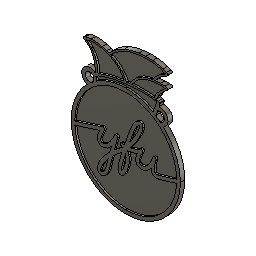
Karnevalsorden (Autodesk Fusion 360 design; units mm, degrees)
Autodesk Fusion 360 part; units mm, degrees
(part 1 of 2)
sketch "Skizze1" plane through (0, 0, 0) normal (0, 0, 1) x (1, 0, 0)
  circle A0 centre (0, 0) radius 30 construction
  spline S0 degree 3 poles (-17.616, 24.4973) (-17.4482, 25.7266) (-17.6451, 26.9772) (-18.1766, 28.0978) knots 0 0 0 0 1 1 1 1
  spline S1 degree 3 poles (-18.1766, 28.0978) (-18.2234, 28.1401) (-18.2504, 28.1872) (-18.216, 28.2338) knots 0 0 0 0 1 1 1 1
  spline S2 degree 3 poles (-18.216, 28.2338) (-18.206, 28.2901) (-18.1253, 28.3306) (-18.0025, 28.3483) knots 0 0 0 0 1 1 1 1
  spline S3 degree 3 poles (-18.0025, 28.3483) (-17.6832, 28.4795) (-17.2924, 28.5436) (-17.0288, 28.7547) knots 0 0 0 0 1 1 1 1
  spline S4 degree 3 poles (-17.0288, 28.7547) (-16.8383, 28.9055) (-16.8992, 29.178) (-16.8992, 29.395) knots 0 0 0 0 1 1 1 1
  spline S5 degree 3 poles (-16.8992, 29.395) (-16.8992, 29.6755) (-16.9122, 29.9401) (-16.9122, 30.2046) knots 0 0 0 0 1 1 1 1
  spline S6 degree 3 poles (-16.9122, 30.2046) (-16.928, 30.7179) (-16.9609, 31.2392) (-17.0103, 31.7683) knots 0 0 0 0 1 1 1 1
  spline S7 degree 3 poles (-17.0103, 31.7683) (-17.0939, 32.675) (-17.244, 33.5744) (-17.4599, 34.4591) knots 0 0 0 0 1 1 1 1
  spline S8 degree 3 poles (-17.4599, 34.4591) (-17.7848, 35.8265) (-18.3203, 37.1351) (-19.0474, 38.3379) knots 0 0 0 0 1 1 1 1
  spline S9 degree 3 poles (-19.0474, 38.3379) (-19.9946, 39.8752) (-21.286, 40.9838) (-22.7174, 42.0421) knots 0 0 0 0 1 1 1 1
  spline S10 degree 3 poles (-22.7174, 42.0421) (-22.982, 42.2352) (-23.4794, 42.526) (-23.5111, 42.8938) knots 0 0 0 0 1 1 1 1
  spline S11 degree 3 poles (-23.5111, 42.8938) (-23.5291, 42.9983) (-23.4712, 43.1023) (-23.3733, 43.1428) knots 0 0 0 0 1 1 1 1
  spline S12 degree 3 poles (-23.3733, 43.1428) (-22.9568, 43.3838) (-22.5126, 43.5727) (-22.0504, 43.7061) knots 0 0 0 0 1 1 1 1
  spline S13 degree 3 poles (-22.0504, 43.7061) (-21.0862, 44.014) (-20.085, 44.1921) (-19.0738, 44.2352) knots 0 0 0 0 1 1 1 1
  spline S14 degree 3 poles (-19.0738, 44.2352) (-17.0386, 44.3223) (-15.0027, 44.0916) (-13.0389, 43.5502) knots 0 0 0 0 1 1 1 1
  spline S15 degree 3 poles (-13.0389, 43.5502) (-12.2002, 43.3174) (-11.3906, 43.021) (-10.5677, 42.7565) knots 0 0 0 0 1 1 1 1
  spline S16 degree 3 poles (-10.5677, 42.7565) (-10.1375, 42.6186) (-9.7131, 42.463) (-9.294, 42.2948) knots 0 0 0 0 1 1 1 1
  spline S17 degree 3 poles (-9.294, 42.2948) (-9.2924, 42.3114) (-9.2961, 42.3281) (-9.2816, 42.3435) knots 0 0 0 0 1 1 1 1
  spline S18 degree 3 poles (-9.2816, 42.3435) (-9.0064, 42.6477) (-8.7262, 42.9443) (-8.4352, 43.2354) knots 0 0 0 0 1 1 1 1
  spline S19 degree 3 poles (-8.4352, 43.2354) (-6.2484, 45.4031) (-3.6817, 47.1504) (-0.8631, 48.3897) knots 0 0 0 0 1 1 1 1
  spline S20 degree 3 poles (-0.8631, 48.3897) (1.7507, 49.5303) (4.5117, 50.2984) (7.339, 50.6725) knots 0 0 0 0 1 1 1 1
  spline S21 degree 3 poles (7.339, 50.6725) (8.5974, 50.8424) (9.8637, 50.9437) (11.131, 50.9755) knots 0 0 0 0 1 1 1 1
  spline S22 degree 3 poles (11.131, 50.9755) (12.3986, 51.0072) (13.6678, 50.9699) (14.9331, 50.8633) knots 0 0 0 0 1 1 1 1
  spline S23 degree 3 poles (14.9331, 50.8633) (16.9063, 50.7289) (18.8571, 50.3593) (20.7428, 49.7626) knots 0 0 0 0 1 1 1 1
  spline S24 degree 3 poles (20.7428, 49.7626) (21.367, 49.5684) (21.9689, 49.3078) (22.5372, 48.985) knots 0 0 0 0 1 1 1 1
  spline S25 degree 3 poles (22.5372, 48.985) (22.9129, 48.8014) (23.2272, 48.5125) (23.4421, 48.154) knots 0 0 0 0 1 1 1 1
  spline S26 degree 3 poles (23.4421, 48.154) (23.4625, 48.1217) (23.4566, 48.0791) (23.4286, 48.0532) knots 0 0 0 0 1 1 1 1
  spline S27 degree 3 poles (23.4286, 48.0532) (22.9338, 47.4076) (22.2435, 47.003) (21.5477, 46.6141) knots 0 0 0 0 1 1 1 1
  spline S28 degree 3 poles (21.5477, 46.6141) (20.8095, 46.2019) (20.102, 45.7367) (19.431, 45.2224) knots 0 0 0 0 1 1 1 1
  spline S29 degree 3 poles (19.431, 45.2224) (18.1673, 44.2572) (17.0572, 43.111) (16.1147, 41.8323) knots 0 0 0 0 1 1 1 1
  spline S30 degree 3 poles (16.1147, 41.8323) (17.172, 41.9148) (18.2306, 41.99) (19.2908, 42.0365) knots 0 0 0 0 1 1 1 1
  spline S31 degree 3 poles (19.2908, 42.0365) (20.1427, 42.0895) (20.9973, 42.0895) (21.8493, 42.0365) knots 0 0 0 0 1 1 1 1
  spline S32 degree 3 poles (21.8493, 42.0365) (22.2382, 41.9889) (23.6191, 41.8857) (23.3783, 41.1952) knots 0 0 0 0 1 1 1 1
  spline S33 degree 3 poles (23.3783, 41.1952) (23.2611, 40.9414) (23.0865, 40.7189) (22.8679, 40.5446) knots 0 0 0 0 1 1 1 1
  spline S34 degree 3 poles (22.8679, 40.5446) (22.561, 40.2456) (22.2327, 39.9807) (21.9072, 39.7161) knots 0 0 0 0 1 1 1 1
  spline S35 degree 3 poles (21.9072, 39.7161) (21.028, 39.0171) (20.2142, 38.2398) (19.4757, 37.3934) knots 0 0 0 0 1 1 1 1
  spline S36 degree 3 poles (19.4757, 37.3934) (18.7878, 36.5724) (18.1819, 35.6863) (17.6662, 34.7475) knots 0 0 0 0 1 1 1 1
  spline S37 degree 3 poles (17.6662, 34.7475) (17.4387, 34.3242) (17.2297, 33.8876) (16.9836, 33.4722) knots 0 0 0 0 1 1 1 1
  spline S38 degree 3 poles (16.9836, 33.4722) (16.9164, 33.3198) (16.8132, 33.1897) (16.6889, 33.0836) knots 0 0 0 0 1 1 1 1
  spline S39 degree 3 poles (16.6889, 33.0836) (17.0786, 32.9642) (17.4749, 32.8595) (17.875, 32.7555) knots 0 0 0 0 1 1 1 1
  spline S40 degree 3 poles (17.875, 32.7555) (18.2052, 32.7007) (18.5288, 32.6121) (18.8407, 32.4909) knots 0 0 0 0 1 1 1 1
  spline S41 degree 3 poles (18.8407, 32.4909) (18.8778, 32.4724) (18.9891, 32.4009) (18.968, 32.3374) knots 0 0 0 0 1 1 1 1
  spline S42 degree 3 poles (18.968, 32.3374) (18.4362, 30.6335) (17.9279, 28.9188) (17.3458, 27.2281) knots 0 0 0 0 1 1 1 1
  spline S43 degree 3 poles (17.3458, 27.2281) (17.1252, 26.588) (16.9135, 25.8274) (16.5002, 25.2646) knots 0 0 0 0 1 1 1 1
  spline S44 degree 3 poles (16.5002, 25.2646) (24.7248, 19.8761) (30.1625, 10.5768) (30.1625, 0.0175) knots 0 0 0 0 1 1 1 1
  spline S45 degree 3 poles (30.1625, 0.0175) (30.1625, -16.6298) (16.6471, -30.1452) (0, -30.1452) knots 0 0 0 0 1 1 1 1
  spline S46 degree 3 poles (0, -30.1452) (-16.6473, -30.1452) (-30.1628, -16.6298) (-30.1628, 0.0175) knots 0 0 0 0 1 1 1 1
  spline S47 degree 3 poles (-30.1628, 0.0175) (-30.1628, 10.0907) (-25.2143, 19.0173) (-17.616, 24.4973) knots 0 0 0 0 1 1 1 1
  spline S48 degree 3 poles (28.1448, -1.3567) (24.9716, -2.4841) (21.4283, -3.5501) (17.957, -4.4156) knots 0 0 0 0 1 1 1 1
  spline S49 degree 3 poles (17.957, -4.4156) (16.2523, -4.8415) (15.3011, -4.2738) (14.8037, -3.7229) knots 0 0 0 0 1 1 1 1
  spline S50 degree 3 poles (14.8037, -3.7229) (14.2669, -3.1286) (14.0248, -2.2828) (13.961, -1.3535) knots 0 0 0 0 1 1 1 1
  spline S51 degree 3 poles (13.961, -1.3535) (12.6484, -3.012) (10.8701, -4.4166) (8.6122, -4.4166) knots 0 0 0 0 1 1 1 1
  spline S52 degree 3 poles (8.6122, -4.4166) (7.0083, -4.4166) (6.2566, -3.6837) (5.9084, -3.0691) knots 0 0 0 0 1 1 1 1
  spline S53 degree 3 poles (5.9084, -3.0691) (5.1385, -1.7097) (5.6534, 0.3541) (6.3328, 2.035) knots 0 0 0 0 1 1 1 1
  spline S54 degree 3 poles (6.3328, 2.035) (4.913, 1.4151) (3.0406, 0.8081) (1.0112, 0.7097) knots 0 0 0 0 1 1 1 1
  spline S55 degree 3 poles (1.0112, 0.7097) (1.3131, 0.2255) (1.547, -0.3264) (1.7087, -0.9421) knots 0 0 0 0 1 1 1 1
  spline S56 degree 3 poles (1.7087, -0.9421) (2.7152, -4.7773) (0.6628, -10.2869) (-1.2121, -12.1298) knots 0 0 0 0 1 1 1 1
  spline S57 degree 3 poles (-1.2121, -12.1298) (-2.032, -12.9357) (-2.73, -12.9574) (-3.171, -12.833) knots 0 0 0 0 1 1 1 1
  spline S58 degree 3 poles (-3.171, -12.833) (-3.5317, -12.7317) (-3.8314, -12.4785) (-4.0148, -12.12) knots 0 0 0 0 1 1 1 1
  spline S59 degree 3 poles (-4.0148, -12.12) (-4.4678, -11.2341) (-4.49, -9.1381) (-2.1275, -1.6486) knots 0 0 0 0 1 1 1 1
  spline S60 degree 3 poles (-2.1275, -1.6486) (-4.1262, -3.1921) (-5.7976, -4.6307) (-7.1911, -5.9565) knots 0 0 0 0 1 1 1 1
  spline S61 degree 3 poles (-7.1911, -5.9565) (-7.3358, -6.473) (-7.4745, -6.9624) (-7.6033, -7.4101) knots 0 0 0 0 1 1 1 1
  spline S62 degree 3 poles (-7.6033, -7.4101) (-7.697, -7.7353) (-7.815, -8.2716) (-7.9518, -8.8926) knots 0 0 0 0 1 1 1 1
  spline S63 degree 3 poles (-7.9518, -8.8926) (-8.7958, -12.7227) (-9.7933, -16.5697) (-11.8637, -17.854) knots 0 0 0 0 1 1 1 1
  spline S64 degree 3 poles (-11.8637, -17.854) (-12.3235, -18.1392) (-12.8222, -18.284) (-13.3331, -18.284) knots 0 0 0 0 1 1 1 1
  spline S65 degree 3 poles (-13.3331, -18.284) (-13.5583, -18.284) (-13.7859, -18.2559) (-14.0134, -18.1993) knots 0 0 0 0 1 1 1 1
  spline S66 degree 3 poles (-14.0134, -18.1993) (-14.8198, -17.999) (-15.3863, -17.3675) (-15.5681, -16.4665) knots 0 0 0 0 1 1 1 1
  spline S67 degree 3 poles (-15.5681, -16.4665) (-16.0004, -14.3234) (-14.3124, -10.2861) (-8.8403, -4.9746) knots 0 0 0 0 1 1 1 1
  spline S68 degree 3 poles (-8.8403, -4.9746) (-8.5548, -3.9488) (-8.2502, -2.8381) (-7.9552, -1.752) knots 0 0 0 0 1 1 1 1
  spline S69 degree 3 poles (-7.9552, -1.752) (-9.2723, -3.2292) (-10.926, -4.4164) (-12.8373, -4.4164) knots 0 0 0 0 1 1 1 1
  spline S70 degree 3 poles (-12.8373, -4.4164) (-14.2777, -4.4164) (-14.9656, -3.7409) (-15.2892, -3.1739) knots 0 0 0 0 1 1 1 1
  spline S71 degree 3 poles (-15.2892, -3.1739) (-16.1496, -1.6668) (-15.3331, 0.8417) (-14.5137, 2.6544) knots 0 0 0 0 1 1 1 1
  spline S72 degree 3 poles (-14.5137, 2.6544) (-17.9602, 1.5426) (-24.6946, -0.6209) (-28.1286, -1.6639) knots 0 0 0 0 1 1 1 1
  spline S73 degree 3 poles (-28.1286, -1.6639) (-27.2576, -16.4345) (-14.9876, -28.1609) (-0.0003, -28.1609) knots 0 0 0 0 1 1 1 1
  spline S74 degree 3 poles (-0.0003, -28.1609) (15.0916, -28.1609) (27.428, -16.271) (28.1448, -1.3567) knots 0 0 0 0 1 1 1 1
  spline S75 degree 3 poles (-12.8408, -16.2803) (-13.0813, -16.4295) (-13.3054, -16.4671) (-13.5676, -16.402) knots 0 0 0 0 1 1 1 1
  spline S76 degree 3 poles (-13.5676, -16.402) (-13.6067, -16.3922) (-13.6991, -16.3692) (-13.7533, -16.1004) knots 0 0 0 0 1 1 1 1
  spline S77 degree 3 poles (-13.7533, -16.1004) (-13.9348, -15.2013) (-13.2816, -12.6174) (-9.7959, -8.65) knots 0 0 0 0 1 1 1 1
  spline S78 degree 3 poles (-9.7959, -8.65) (-10.2952, -10.9127) (-11.2974, -15.323) (-12.8408, -16.2803) knots 0 0 0 0 1 1 1 1
  spline S79 degree 3 poles (-2.417, -10.7449) (-2.3987, -9.8541) (-2.0709, -7.6197) (-0.3418, -2.1333) knots 0 0 0 0 1 1 1 1
  spline S80 degree 3 poles (-0.3418, -2.1333) (-0.2609, -1.8761) (-0.1786, -1.6181) (-0.0958, -1.3602) knots 0 0 0 0 1 1 1 1
  spline S81 degree 3 poles (-0.0958, -1.3602) (0.0341, -1.8338) (0.1058, -2.3701) (0.1193, -2.9688) knots 0 0 0 0 1 1 1 1
  spline S82 degree 3 poles (0.1193, -2.9688) (0.1924, -6.1959) (-1.4219, -9.6967) (-2.417, -10.7449) knots 0 0 0 0 1 1 1 1
  spline S83 degree 3 poles (28.1715, 0.621) (27.8492, 15.8954) (15.3495, 28.1957) (-0.0003, 28.1957) knots 0 0 0 0 1 1 1 1
  spline S84 degree 3 poles (-0.0003, 28.1957) (-15.4712, 28.1957) (-28.0469, 15.7002) (-28.1771, 0.2578) knots 0 0 0 0 1 1 1 1
  spline S85 degree 3 poles (-28.1771, 0.2578) (-23.2635, 1.7638) (-13.058, 5.0711) (-12.945, 5.1078) knots 0 0 0 0 1 1 1 1
  spline S86 degree 3 poles (-12.945, 5.1078) (-12.5786, 5.2266) (-12.1777, 5.1063) (-11.9369, 4.806) knots 0 0 0 0 1 1 1 1
  spline S87 degree 3 poles (-11.9369, 4.806) (-11.6964, 4.5059) (-11.6665, 4.0879) (-11.8618, 3.7564) knots 0 0 0 0 1 1 1 1
  spline S88 degree 3 poles (-11.8618, 3.7564) (-12.9379, 1.9307) (-14.2602, -1.2427) (-13.6811, -2.256) knots 0 0 0 0 1 1 1 1
  spline S89 degree 3 poles (-13.6811, -2.256) (-13.6374, -2.3325) (-13.5046, -2.5645) (-12.8376, -2.5645) knots 0 0 0 0 1 1 1 1
  spline S90 degree 3 poles (-12.8376, -2.5645) (-9.7613, -2.5645) (-7.0427, 2.5845) (-6.2547, 4.5686) knots 0 0 0 0 1 1 1 1
  spline S91 degree 3 poles (-6.2547, 4.5686) (-6.0738, 5.0237) (-5.5703, 5.2595) (-5.1043, 5.1063) knots 0 0 0 0 1 1 1 1
  spline S92 degree 3 poles (-5.1043, 5.1063) (-4.6389, 4.9531) (-4.3733, 4.4639) (-4.4984, 3.9902) knots 0 0 0 0 1 1 1 1
  spline S93 degree 3 poles (-4.4984, 3.9902) (-4.5114, 3.9413) (-5.3668, 0.7039) (-6.2767, -2.6378) knots 0 0 0 0 1 1 1 1
  spline S94 degree 3 poles (-6.2767, -2.6378) (-5.044, -1.5776) (-3.6695, -0.4749) (-2.1434, 0.665) knots 0 0 0 0 1 1 1 1
  spline S95 degree 3 poles (-2.1434, 0.665) (-2.0529, 0.7324) (-1.96, 0.8047) (-1.8658, 0.8811) knots 0 0 0 0 1 1 1 1
  spline S96 degree 3 poles (-1.8658, 0.8811) (-2.0169, 0.9526) (-2.1765, 1.0142) (-2.3445, 1.0663) knots 0 0 0 0 1 1 1 1
  spline S97 degree 3 poles (-2.3445, 1.0663) (-2.3998, 1.0819) (-2.4553, 1.0981) (-2.5106, 1.1145) knots 0 0 0 0 1 1 1 1
  spline S98 degree 3 poles (-2.5106, 1.1145) (-2.9961, 1.2592) (-3.275, 1.7675) (-3.1366, 2.2548) knots 0 0 0 0 1 1 1 1
  spline S99 degree 3 poles (-3.1366, 2.2548) (-2.9983, 2.7422) (-2.4934, 3.029) (-2.0047, 2.8959) knots 0 0 0 0 1 1 1 1
  spline S100 degree 3 poles (-2.0047, 2.8959) (-1.9434, 2.8795) (-1.8828, 2.8621) (-1.8225, 2.8438) knots 0 0 0 0 1 1 1 1
  spline S101 degree 3 poles (-1.8225, 2.8438) (-1.4555, 2.7427) (-1.0869, 2.6705) (-0.7191, 2.6226) knots 0 0 0 0 1 1 1 1
  spline S102 degree 3 poles (-0.7191, 2.6226) (-0.0122, 4.6909) (0.826, 7.0539) (1.8148, 9.7534) knots 0 0 0 0 1 1 1 1
  spline S103 degree 3 poles (1.8148, 9.7534) (1.9476, 10.1161) (2.0548, 10.4085) (2.1304, 10.6181) knots 0 0 0 0 1 1 1 1
  spline S104 degree 3 poles (2.1304, 10.6181) (3.6716, 14.8823) (5.2631, 17.2956) (6.8601, 17.7909) knots 0 0 0 0 1 1 1 1
  spline S105 degree 3 poles (6.8601, 17.7909) (7.543, 18.002) (8.2219, 17.8862) (8.8236, 17.4546) knots 0 0 0 0 1 1 1 1
  spline S106 degree 3 poles (8.8236, 17.4546) (9.1324, 17.2332) (9.502, 16.7876) (9.5102, 15.9222) knots 0 0 0 0 1 1 1 1
  spline S107 degree 3 poles (9.5102, 15.9222) (9.5348, 13.356) (6.0074, 7.0859) (2.481, 2.7525) knots 0 0 0 0 1 1 1 1
  spline S108 degree 3 poles (2.481, 2.7525) (5.5062, 3.3335) (7.8941, 4.9634) (7.9288, 4.9877) knots 0 0 0 0 1 1 1 1
  spline S109 degree 3 poles (7.9288, 4.9877) (8.2873, 5.2359) (8.7701, 5.2007) (9.0887, 4.9028) knots 0 0 0 0 1 1 1 1
  spline S110 degree 3 poles (9.0887, 4.9028) (9.4073, 4.6051) (9.4747, 4.1252) (9.2506, 3.7508) knots 0 0 0 0 1 1 1 1
  spline S111 degree 3 poles (9.2506, 3.7508) (8.1986, 1.9929) (6.921, -1.1009) (7.5197, -2.1568) knots 0 0 0 0 1 1 1 1
  spline S112 degree 3 poles (7.5197, -2.1568) (7.5769, -2.2576) (7.751, -2.5645) (8.6117, -2.5645) knots 0 0 0 0 1 1 1 1
  spline S113 degree 3 poles (8.6117, -2.5645) (11.7758, -2.5645) (14.0769, 1.9371) (14.8741, 4.1167) knots 0 0 0 0 1 1 1 1
  spline S114 degree 3 poles (14.8741, 4.1167) (14.9333, 4.2953) (14.9839, 4.439) (15.0207, 4.5411) knots 0 0 0 0 1 1 1 1
  spline S115 degree 3 poles (15.0207, 4.5411) (15.1921, 5.0166) (15.7125, 5.2661) (16.1914, 5.1031) knots 0 0 0 0 1 1 1 1
  spline S116 degree 3 poles (16.1914, 5.1031) (16.6695, 4.9393) (16.9283, 4.4226) (16.7727, 3.9416) knots 0 0 0 0 1 1 1 1
  spline S117 degree 3 poles (16.7727, 3.9416) (16.7614, 3.9066) (16.7235, 3.7913) (16.6584, 3.6119) knots 0 0 0 0 1 1 1 1
  spline S118 degree 3 poles (16.6584, 3.6119) (15.9695, 1.5582) (15.3808, -1.6001) (16.1777, -2.4817) knots 0 0 0 0 1 1 1 1
  spline S119 degree 3 poles (16.1777, -2.4817) (16.4071, -2.7355) (16.855, -2.7818) (17.5083, -2.6188) knots 0 0 0 0 1 1 1 1
  spline S120 degree 3 poles (17.5083, -2.6188) (21.1622, -1.7073) (24.8946, -0.5717) (28.1715, 0.621) knots 0 0 0 0 1 1 1 1
  spline S121 degree 3 poles (3.5534, 9.1163) (3.6872, 9.4822) (3.7954, 9.7772) (3.8719, 9.9886) knots 0 0 0 0 1 1 1 1
  spline S122 degree 3 poles (3.8719, 9.9886) (5.3552, 14.0926) (6.7043, 15.8039) (7.4086, 16.0222) knots 0 0 0 0 1 1 1 1
  spline S123 degree 3 poles (7.4086, 16.0222) (7.4433, 16.0328) (7.4792, 16.0431) (7.5155, 16.0415) knots 0 0 0 0 1 1 1 1
  spline S124 degree 3 poles (7.5155, 16.0415) (7.5642, 16.0394) (7.6015, 16.0317) (7.6565, 16.0037) knots 0 0 0 0 1 1 1 1
  spline S125 degree 3 poles (7.6565, 16.0037) (7.7478, 15.4322) (7.148, 13.1366) (4.6027, 8.971) knots 0 0 0 0 1 1 1 1
  spline S126 degree 3 poles (4.6027, 8.971) (3.8394, 7.7219) (3.0274, 6.5186) (2.2148, 5.4203) knots 0 0 0 0 1 1 1 1
  spline S127 degree 3 poles (2.2148, 5.4203) (2.7525, 6.9295) (3.2247, 8.2191) (3.5534, 9.1163) knots 0 0 0 0 1 1 1 1
  spline S128 degree 3 poles (15.0596, 26.152) (10.6273, 28.7134) (5.4835, 30.18) (0, 30.18) knots 0 0 0 0 1 1 1 1
  spline S129 degree 3 poles (0, 30.18) (-5.9664, 30.18) (-11.5305, 28.4438) (-16.2139, 25.4498) knots 0 0 0 0 1 1 1 1
  spline S130 degree 3 poles (-16.2139, 25.4498) (-16.3237, 26.1592) (-16.3161, 26.8923) (-16.5132, 27.5858) knots 0 0 0 0 1 1 1 1
  spline S131 degree 3 poles (-16.5132, 27.5858) (-14.6418, 28.923) (-12.3076, 29.6376) (-10.1126, 30.2388) knots 0 0 0 0 1 1 1 1
  spline S132 degree 3 poles (-10.1126, 30.2388) (-7.775, 30.8679) (-5.4054, 31.3717) (-3.0139, 31.7472) knots 0 0 0 0 1 1 1 1
  spline S133 degree 3 poles (-3.0139, 31.7472) (0.3421, 32.302) (3.7293, 32.6502) (7.1279, 32.7896) knots 0 0 0 0 1 1 1 1
  spline S134 degree 3 poles (7.1279, 32.7896) (7.9923, 32.8227) (8.8643, 32.8446) (9.7385, 32.8468) knots 0 0 0 0 1 1 1 1
  spline S135 degree 3 poles (9.7385, 32.8468) (12.228, 32.8528) (14.7352, 32.6877) (17.1508, 32.1472) knots 0 0 0 0 1 1 1 1
  spline S136 degree 3 poles (17.1508, 32.1472) (16.4716, 30.3094) (15.948, 28.4176) (15.2188, 26.6007) knots 0 0 0 0 1 1 1 1
  spline S137 degree 3 poles (15.2188, 26.6007) (15.177, 26.4939) (15.1257, 26.3219) (15.0596, 26.152) knots 0 0 0 0 1 1 1 1
  spline S138 degree 3 poles (-17.5363, 43.233) (-16.1285, 43.2409) (-14.7238, 43.084) (-13.3511, 42.7641) knots 0 0 0 0 1 1 1 1
  spline S139 degree 3 poles (-13.3511, 42.7641) (-9.8904, 41.9916) (-6.4717, 40.399) (-3.9423, 37.8852) knots 0 0 0 0 1 1 1 1
  spline S140 degree 3 poles (-3.9423, 37.8852) (-2.5643, 36.5562) (-1.5401, 34.906) (-0.9538, 33.0846) knots 0 0 0 0 1 1 1 1
  spline S141 degree 3 poles (-0.9538, 33.0846) (-2.5556, 32.7084) (-4.182, 32.4695) (-5.7944, 32.184) knots 0 0 0 0 1 1 1 1
  spline S142 degree 3 poles (-5.7944, 32.184) (-7.833, 31.8371) (-9.8467, 31.3556) (-11.8221, 30.7441) knots 0 0 0 0 1 1 1 1
  spline S143 degree 3 poles (-11.8221, 30.7441) (-13.0127, 30.3697) (-14.1856, 29.9453) (-15.3469, 29.4858) knots 0 0 0 0 1 1 1 1
  spline S144 degree 3 poles (-15.3469, 29.4858) (-15.3924, 31.331) (-15.6768, 33.1629) (-16.1981, 34.9351) knots 0 0 0 0 1 1 1 1
  spline S145 degree 3 poles (-16.1981, 34.9351) (-16.7918, 36.8025) (-17.785, 38.5178) (-19.1085, 39.9622) knots 0 0 0 0 1 1 1 1
  spline S146 degree 3 poles (-19.1085, 39.9622) (-19.9379, 40.8576) (-20.8642, 41.6577) (-21.866, 42.3551) knots 0 0 0 0 1 1 1 1
  spline S147 degree 3 poles (-21.866, 42.3551) (-20.696, 42.893) (-19.4286, 43.1893) (-18.1398, 43.2198) knots 0 0 0 0 1 1 1 1
  spline S148 degree 3 poles (-18.1398, 43.2198) (-17.9387, 43.2274) (-17.7374, 43.2319) (-17.5363, 43.233) knots 0 0 0 0 1 1 1 1
  spline S149 degree 3 poles (13.1352, 49.9976) (13.694, 49.9904) (14.2534, 49.9658) (14.8135, 49.919) knots 0 0 0 0 1 1 1 1
  spline S150 degree 3 poles (14.8135, 49.919) (17.2601, 49.7124) (19.6596, 49.0932) (21.7734, 47.8396) knots 0 0 0 0 1 1 1 1
  spline S151 degree 3 poles (21.7734, 47.8396) (19.8072, 46.7763) (18.0078, 45.4288) (16.4383, 43.8362) knots 0 0 0 0 1 1 1 1
  spline S152 degree 3 poles (16.4383, 43.8362) (16.0327, 43.4182) (15.6483, 42.9824) (15.285, 42.5292) knots 0 0 0 0 1 1 1 1
  spline S153 degree 3 poles (15.285, 42.5292) (15.1236, 42.3281) (15.0201, 42.1238) (14.8455, 41.9415) knots 0 0 0 0 1 1 1 1
  spline S154 degree 3 poles (14.8455, 41.9415) (14.6442, 41.7661) (14.4052, 41.6391) (14.147, 41.5709) knots 0 0 0 0 1 1 1 1
  spline S155 degree 3 poles (14.147, 41.5709) (13.2183, 41.2904) (12.2449, 41.1613) (11.3109, 40.8938) knots 0 0 0 0 1 1 1 1
  spline S156 degree 3 poles (11.3109, 40.8938) (9.8803, 40.4945) (8.5222, 39.8693) (7.289, 39.0417) knots 0 0 0 0 1 1 1 1
  spline S157 degree 3 poles (7.289, 39.0417) (5.1935, 37.6185) (3.5187, 35.6868) (2.1243, 33.5884) knots 0 0 0 0 1 1 1 1
  spline S158 degree 3 poles (2.1243, 33.5884) (2.1111, 33.5704) (2.1042, 33.549) (2.1042, 33.5265) knots 0 0 0 0 1 1 1 1
  spline S159 degree 3 poles (2.1042, 33.5265) (2.1042, 33.5146) (2.1093, 33.5037) (2.113, 33.4931) knots 0 0 0 0 1 1 1 1
  spline S160 degree 3 poles (2.113, 33.4931) (1.5452, 33.4384) (0.9784, 33.3728) (0.412, 33.3021) knots 0 0 0 0 1 1 1 1
  spline S161 degree 3 poles (0.412, 33.3021) (-1.2692, 36.8801) (-4.228, 39.7966) (-7.7391, 41.5897) knots 0 0 0 0 1 1 1 1
  spline S162 degree 3 poles (-7.7391, 41.5897) (-8.0063, 41.7262) (-8.2775, 41.8545) (-8.5508, 41.9781) knots 0 0 0 0 1 1 1 1
  spline S163 degree 3 poles (-8.5508, 41.9781) (-8.4463, 41.9873) (-8.3497, 42.0111) (-8.2868, 42.0715) knots 0 0 0 0 1 1 1 1
  spline S164 degree 3 poles (-8.2868, 42.0715) (-5.4054, 44.8705) (-2.0458, 47.1697) (1.7828, 48.4638) knots 0 0 0 0 1 1 1 1
  spline S165 degree 3 poles (1.7828, 48.4638) (3.8349, 49.1356) (5.9597, 49.5623) (8.1121, 49.7341) knots 0 0 0 0 1 1 1 1
  spline S166 degree 3 poles (8.1121, 49.7341) (9.7869, 49.8849) (11.4586, 50.019) (13.1352, 49.9976) knots 0 0 0 0 1 1 1 1
  spline S167 degree 3 poles (18.6288, 41.1362) (19.648, 41.1552) (20.6655, 41.066) (21.6704, 40.8906) knots 0 0 0 0 1 1 1 1
  spline S168 degree 3 poles (21.6704, 40.8906) (20.5936, 39.8124) (19.4352, 38.8134) (18.4042, 37.6871) knots 0 0 0 0 1 1 1 1
  spline S169 degree 3 poles (18.4042, 37.6871) (17.2262, 36.3972) (16.2764, 34.9174) (15.5893, 33.3122) knots 0 0 0 0 1 1 1 1
  spline S170 degree 3 poles (15.5893, 33.3122) (11.5356, 33.8114) (7.4456, 33.9072) (3.3782, 33.5995) knots 0 0 0 0 1 1 1 1
  spline S171 degree 3 poles (3.3782, 33.5995) (4.1693, 34.4943) (4.8025, 35.5236) (5.6065, 36.4067) knots 0 0 0 0 1 1 1 1
  spline S172 degree 3 poles (5.6065, 36.4067) (6.6072, 37.4711) (7.7957, 38.3422) (9.1122, 38.9758) knots 0 0 0 0 1 1 1 1
  spline S173 degree 3 poles (9.1122, 38.9758) (11.6467, 40.2749) (14.6182, 40.8626) (17.4387, 41.069) knots 0 0 0 0 1 1 1 1
  spline S174 degree 3 poles (17.4387, 41.069) (17.835, 41.1063) (18.2319, 41.1285) (18.6288, 41.1362) knots 0 0 0 0 1 1 1 1
  arc A1 (14.4395, 26.5006) -> (14.4198, 26.3072) centre (18.9053, 25.9469) ccw
  arc A2 (20.6228, 21.7876) -> (18.3737, 30.4154) centre (18.9053, 25.9469) ccw
  arc A3 (18.9867, 23.4482) -> (17.6404, 28.1033) centre (18.9053, 25.9469) ccw
  arc A4 (-16.8935, 29.0389) -> (-21.1061, 21.3197) centre (-19.8405, 25.6381) ccw
  arc A5 (-15.3427, 25.7798) -> (-15.3535, 25.9798) centre (-19.8405, 25.6381) ccw
  arc A6 (-17.7936, 27.0735) -> (-19.2887, 23.1997) centre (-19.8405, 25.6381) ccw
  dimension "d1" = 60
  dimension "d2" = 5
  dimension "d4" = 5
  constraint coincident A0.centre origin
  constraint coincident S43.end A3
  constraint concentric A1 A3
  constraint coincident S42 A2.end
  constraint coincident S128 A1.start
  constraint coincident A0 A1.end
  constraint concentric A1 A2
  constraint coincident A0 A2.start
  constraint coincident S42 A3.end
  constraint concentric A4 A6
  constraint coincident S4 A4.start
  constraint coincident S129 A5.end
  constraint coincident A0 A5.start
  constraint concentric A4 A5
  constraint coincident A0 A4.end
  constraint coincident S47 A6.end
  constraint coincident S0 A6.start
  constraint coincident S44 A3.start
  measures "d1" diameter of A0
  measures "d2" diameter of A3
  measures "d4" diameter of A6
extrude "Extrusion1" add sketch "Skizze1" against normal blind 1.5 contours S0 S1 S2 S3 S4 S5 S6 S7 S8 S9 S10 S11 S12 S13 S14 S15 S16 S17 S18 S19 S20 S21 S22 S23 S24 S25 S26 S27 S28 S29 S30 S31 S32 S33 S34 S35 S36 S37 S38 S39 S40 S41 S42 S43 S44 S45 S46 S47 | S0 S1 S2 S3 S4 S47 A4 A6 | S42 S44 A2 A3 | S48 S49 S50 S51 S52 S53 S54 S55 S56 S57 S58 S59 S60 S61 S62 S63 S64 S65 S66 S67 S68 S69 S70 S71 S72 S73 S74 | S75 S76 S77 S78 | S79 S80 S81 S82 | S83 S84 S85 S86 S87 S88 S89 S90 S91 S92 S93 S94 S95 S96 S97 S98 S99 S100 S101 S102 S103 S104 S105 S106 S107 S108 S109 S110 S111 S112 S113 S114 S115 S116 S117 S118 S119 S120 | S121 S122 S123 S124 S125 S126 S127 | S128 S129 S130 S131 S132 S133 S134 S135 S136 S137 | S138 S139 S140 S141 S142 S143 S144 S145 S146 S147 S148 | S149 S150 S151 S152 S153 S154 S155 S156 S157 S158 S159 S160 S161 S162 S163 S164 S165 S166 | S167 S168 S169 S170 S171 S172 S173 S174 makes body 1
extrude "Extrusion2" add sketch "Skizze1" along normal blind 1 contours S0 S1 S2 S3 S4 S5 S6 S7 S8 S9 S10 S11 S12 S13 S14 S15 S16 S17 S18 S19 S20 S21 S22 S23 S24 S25 S26 S27 S28 S29 S30 S31 S32 S33 S34 S35 S36 S37 S38 S39 S40 S41 S42 S43 S44 S45 S46 S47 | S0 S1 S2 S3 S4 S47 A4 A6 | S42 S44 A2 A3 bodies 1
sketch "Skizze2" plane through (0, 0, 0) normal (0, 0, 1) x (1, 0, 0)
  circle A0 centre (0, 0) radius 30 construction
  spline S0 degree 3 poles (-17.4432, 23.7028) (-17.4688, 23.7319) (-17.4815, 23.7663) (-17.4763, 23.8068) knots 0 0 0 0 1 1 1 1
  spline S1 degree 3 poles (-17.4763, 23.8068) (-17.2897, 25.0604) (-17.4837, 26.3397) (-18.0261, 27.4835) knots 0 0 0 0 1 1 1 1
  spline S2 degree 3 poles (-18.0261, 27.4835) (-18.0729, 27.5258) (-18.0999, 27.5729) (-18.0655, 27.6195) knots 0 0 0 0 1 1 1 1
  spline S3 degree 3 poles (-18.0655, 27.6195) (-18.0554, 27.6758) (-17.9747, 27.7163) (-17.852, 27.734) knots 0 0 0 0 1 1 1 1
  spline S4 degree 3 poles (-17.852, 27.734) (-17.5326, 27.8653) (-17.1418, 27.9293) (-16.8783, 28.1404) knots 0 0 0 0 1 1 1 1
  spline S5 degree 3 poles (-16.8783, 28.1404) (-16.6878, 28.2912) (-16.7487, 28.5638) (-16.7487, 28.7807) knots 0 0 0 0 1 1 1 1
  spline S6 degree 3 poles (-16.7487, 28.7807) (-16.7487, 29.0612) (-16.7616, 29.3258) (-16.7616, 29.5903) knots 0 0 0 0 1 1 1 1
  spline S7 degree 3 poles (-16.7616, 29.5903) (-16.7775, 30.1036) (-16.8103, 30.6249) (-16.8598, 31.154) knots 0 0 0 0 1 1 1 1
  spline S8 degree 3 poles (-16.8598, 31.154) (-16.9434, 32.0608) (-17.0934, 32.9601) (-17.3093, 33.8448) knots 0 0 0 0 1 1 1 1
  spline S9 degree 3 poles (-17.3093, 33.8448) (-17.6342, 35.2122) (-18.1697, 36.5208) (-18.8968, 37.7236) knots 0 0 0 0 1 1 1 1
  spline S10 degree 3 poles (-18.8968, 37.7236) (-19.844, 39.2609) (-21.1354, 40.3695) (-22.5668, 41.4278) knots 0 0 0 0 1 1 1 1
  spline S11 degree 3 poles (-22.5668, 41.4278) (-22.8314, 41.6209) (-23.3288, 41.9117) (-23.3606, 42.2795) knots 0 0 0 0 1 1 1 1
  spline S12 degree 3 poles (-23.3606, 42.2795) (-23.3786, 42.384) (-23.3206, 42.488) (-23.2227, 42.5285) knots 0 0 0 0 1 1 1 1
  spline S13 degree 3 poles (-23.2227, 42.5285) (-22.8063, 42.7695) (-22.3621, 42.9584) (-21.8998, 43.0918) knots 0 0 0 0 1 1 1 1
  spline S14 degree 3 poles (-21.8998, 43.0918) (-20.9357, 43.3997) (-19.9345, 43.5778) (-18.9233, 43.6209) knots 0 0 0 0 1 1 1 1
  spline S15 degree 3 poles (-18.9233, 43.6209) (-16.8881, 43.708) (-14.8521, 43.4773) (-12.8884, 42.9359) knots 0 0 0 0 1 1 1 1
  spline S16 degree 3 poles (-12.8884, 42.9359) (-12.0497, 42.7031) (-11.24, 42.4068) (-10.4172, 42.1422) knots 0 0 0 0 1 1 1 1
  spline S17 degree 3 poles (-10.4172, 42.1422) (-9.987, 42.0043) (-9.5626, 41.8488) (-9.1435, 41.6805) knots 0 0 0 0 1 1 1 1
  spline S18 degree 3 poles (-9.1435, 41.6805) (-9.1419, 41.6971) (-9.1456, 41.7138) (-9.131, 41.7292) knots 0 0 0 0 1 1 1 1
  spline S19 degree 3 poles (-9.131, 41.7292) (-8.8559, 42.0334) (-8.5757, 42.33) (-8.2846, 42.6211) knots 0 0 0 0 1 1 1 1
  spline S20 degree 3 poles (-8.2846, 42.6211) (-6.0979, 44.7888) (-3.5311, 46.5361) (-0.7125, 47.7754) knots 0 0 0 0 1 1 1 1
  spline S21 degree 3 poles (-0.7125, 47.7754) (1.9013, 48.916) (4.6622, 49.6841) (7.4896, 50.0582) knots 0 0 0 0 1 1 1 1
  spline S22 degree 3 poles (7.4896, 50.0582) (8.7479, 50.2281) (10.0142, 50.3294) (11.2816, 50.3612) knots 0 0 0 0 1 1 1 1
  spline S23 degree 3 poles (11.2816, 50.3612) (12.5492, 50.3929) (13.8184, 50.3556) (15.0836, 50.249) knots 0 0 0 0 1 1 1 1
  spline S24 degree 3 poles (15.0836, 50.249) (17.0569, 50.1146) (19.0077, 49.745) (20.8934, 49.1483) knots 0 0 0 0 1 1 1 1
  spline S25 degree 3 poles (20.8934, 49.1483) (21.5175, 48.9541) (22.1194, 48.6935) (22.6878, 48.3707) knots 0 0 0 0 1 1 1 1
  spline S26 degree 3 poles (22.6878, 48.3707) (23.0635, 48.1871) (23.3778, 47.8982) (23.5926, 47.5397) knots 0 0 0 0 1 1 1 1
  spline S27 degree 3 poles (23.5926, 47.5397) (23.613, 47.5074) (23.6072, 47.4648) (23.5791, 47.4389) knots 0 0 0 0 1 1 1 1
  spline S28 degree 3 poles (23.5791, 47.4389) (23.0844, 46.7933) (22.3941, 46.3887) (21.6982, 45.9998) knots 0 0 0 0 1 1 1 1
  spline S29 degree 3 poles (21.6982, 45.9998) (20.96, 45.5876) (20.2525, 45.1224) (19.5815, 44.6081) knots 0 0 0 0 1 1 1 1
  spline S30 degree 3 poles (19.5815, 44.6081) (18.3179, 43.6429) (17.2077, 42.4967) (16.2653, 41.218) knots 0 0 0 0 1 1 1 1
  spline S31 degree 3 poles (16.2653, 41.218) (17.3225, 41.3005) (18.3811, 41.3757) (19.4413, 41.4222) knots 0 0 0 0 1 1 1 1
  spline S32 degree 3 poles (19.4413, 41.4222) (20.2933, 41.4752) (21.1479, 41.4752) (21.9998, 41.4222) knots 0 0 0 0 1 1 1 1
  spline S33 degree 3 poles (21.9998, 41.4222) (22.3888, 41.3746) (23.7696, 41.2714) (23.5289, 40.5809) knots 0 0 0 0 1 1 1 1
  spline S34 degree 3 poles (23.5289, 40.5809) (23.4117, 40.3271) (23.237, 40.1046) (23.0185, 39.9303) knots 0 0 0 0 1 1 1 1
  spline S35 degree 3 poles (23.0185, 39.9303) (22.7116, 39.6313) (22.3832, 39.3664) (22.0578, 39.1018) knots 0 0 0 0 1 1 1 1
  spline S36 degree 3 poles (22.0578, 39.1018) (21.1786, 38.4028) (20.3647, 37.6255) (19.6263, 36.7791) knots 0 0 0 0 1 1 1 1
  spline S37 degree 3 poles (19.6263, 36.7791) (18.9383, 35.9581) (18.3325, 35.072) (17.8168, 34.1332) knots 0 0 0 0 1 1 1 1
  spline S38 degree 3 poles (17.8168, 34.1332) (17.5892, 33.7099) (17.3802, 33.2733) (17.1342, 32.8579) knots 0 0 0 0 1 1 1 1
  spline S39 degree 3 poles (17.1342, 32.8579) (17.0669, 32.7055) (16.9638, 32.5754) (16.8394, 32.4693) knots 0 0 0 0 1 1 1 1
  spline S40 degree 3 poles (16.8394, 32.4693) (17.2291, 32.3499) (17.6255, 32.2452) (18.0255, 32.1412) knots 0 0 0 0 1 1 1 1
  spline S41 degree 3 poles (18.0255, 32.1412) (18.3557, 32.0864) (18.6793, 31.9978) (18.9913, 31.8766) knots 0 0 0 0 1 1 1 1
  spline S42 degree 3 poles (18.9913, 31.8766) (19.0283, 31.8581) (19.1397, 31.7866) (19.1185, 31.7231) knots 0 0 0 0 1 1 1 1
  spline S43 degree 3 poles (19.1185, 31.7231) (18.5867, 30.0192) (18.0784, 28.3045) (17.4964, 26.6138) knots 0 0 0 0 1 1 1 1
  spline S44 degree 3 poles (17.4964, 26.6138) (17.2582, 25.9232) (17.0307, 25.0924) (16.5492, 24.5209) knots 0 0 0 0 1 1 1 1
  spline S45 degree 3 poles (16.5492, 24.5209) (16.5145, 24.4804) (16.4801, 24.4431) (16.446, 24.409) knots 0 0 0 0 1 1 1 1
  spline S46 degree 3 poles (16.446, 24.409) (24.2414, 19.1269) (29.3688, 10.1972) (29.3688, 0.0798) knots 0 0 0 0 1 1 1 1
  spline S47 degree 3 poles (29.3688, 0.0798) (29.3688, -16.1294) (16.2092, -29.289) (0, -29.289) knots 0 0 0 0 1 1 1 1
  spline S48 degree 3 poles (0, -29.289) (-16.2089, -29.289) (-29.3688, -16.1294) (-29.3688, 0.0798) knots 0 0 0 0 1 1 1 1
  spline S49 degree 3 poles (-29.3688, 0.0798) (-29.3688, 9.7596) (-24.6753, 18.3522) (-17.4432, 23.7028) knots 0 0 0 0 1 1 1 1
  spline S50 degree 3 poles (23.7546, -14.3247) (17.013, -15.963) (9.0474, -17.3539) (2.3191, -17.3541) knots 0 0 0 0 1 1 1 1
  spline S51 degree 3 poles (2.3191, -17.3541) (-2.6136, -17.3541) (-6.88, -16.607) (-9.5123, -14.662) knots 0 0 0 0 1 1 1 1
  spline S52 degree 3 poles (-9.5123, -14.662) (-9.8274, -14.4289) (-10.1169, -14.1821) (-10.3799, -13.9209) knots 0 0 0 0 1 1 1 1
  spline S53 degree 3 poles (-10.3799, -13.9209) (-15.5173, -14.8083) (-20.4359, -14.6065) (-23.8416, -14.1805) knots 0 0 0 0 1 1 1 1
  spline S54 degree 3 poles (-23.8416, -14.1805) (-18.9854, -22.277) (-10.1211, -27.7012) (0, -27.7012) knots 0 0 0 0 1 1 1 1
  spline S55 degree 3 poles (0, -27.7012) (10.06, -27.7012) (18.8783, -22.3426) (23.7546, -14.3247) knots 0 0 0 0 1 1 1 1
  spline S56 degree 3 poles (24.9499, -12.1448) (26.7631, -8.4546) (27.7813, -4.3052) (27.7813, 0.08) knots 0 0 0 0 1 1 1 1
  spline S57 degree 3 poles (27.7813, 0.08) (27.7813, 15.4126) (15.3329, 27.861) (0, 27.861) knots 0 0 0 0 1 1 1 1
  spline S58 degree 3 poles (0, 27.861) (-0.871, 27.861) (-1.7328, 27.8208) (-2.5852, 27.742) knots 0 0 0 0 1 1 1 1
  line L0 (-2.5852, 27.742) -> (-3.9293, 27.5845)
  spline S59 degree 3 poles (-3.9293, 27.5845) (-17.4048, 25.6732) (-27.7812, 14.0786) (-27.7812, 0.08) knots 0 0 0 0 1 1 1 1
  spline S60 degree 3 poles (-27.7812, 0.08) (-27.7812, -4.3176) (-26.7573, -8.4776) (-24.9343, -12.176) knots 0 0 0 0 1 1 1 1
  spline S61 degree 3 poles (-24.9343, -12.176) (-21.9083, -12.6689) (-16.9299, -13.0576) (-11.6083, -12.2646) knots 0 0 0 0 1 1 1 1
  spline S62 degree 3 poles (-11.6083, -12.2646) (-12.1089, -11.3005) (-12.3611, -10.2091) (-12.3611, -8.9981) knots 0 0 0 0 1 1 1 1
  spline S63 degree 3 poles (-12.3611, -8.9981) (-12.3611, -7.1598) (-12.3079, -2.9904) (-12.2693, 0.0536) knots 0 0 0 0 1 1 1 1
  spline S64 degree 3 poles (-12.2693, 0.0536) (-12.2499, 1.5673) (-12.2341, 2.8153) (-12.2293, 3.4008) knots 0 0 0 0 1 1 1 1
  spline S65 degree 3 poles (-12.2293, 3.4008) (-12.5045, 3.4307) (-12.9582, 3.4141) (-13.2572, 3.4032) knots 0 0 0 0 1 1 1 1
  spline S66 degree 3 poles (-13.2572, 3.4032) (-14.1983, 3.3685) (-15.1707, 3.3326) (-15.7771, 3.9173) knots 0 0 0 0 1 1 1 1
  spline S67 degree 3 poles (-15.7771, 3.9173) (-16.0681, 4.1975) (-16.2219, 4.5711) (-16.2219, 4.9965) knots 0 0 0 0 1 1 1 1
  spline S68 degree 3 poles (-16.2219, 4.9965) (-16.2219, 5.4357) (-16.0523, 6.0342) (-14.024, 8.0599) knots 0 0 0 0 1 1 1 1
  spline S69 degree 3 poles (-14.024, 8.0599) (-12.7841, 9.2979) (-11.1654, 10.7491) (-9.4657, 12.1448) knots 0 0 0 0 1 1 1 1
  spline S70 degree 3 poles (-9.4657, 12.1448) (-6.8932, 14.2588) (-2.2381, 17.8045) (0.0278, 17.8045) knots 0 0 0 0 1 1 1 1
  spline S71 degree 3 poles (0.0278, 17.8045) (2.4178, 17.8045) (7.0279, 14.2911) (9.5631, 12.1966) knots 0 0 0 0 1 1 1 1
  spline S72 degree 3 poles (9.5631, 12.1966) (11.2477, 10.8052) (12.8439, 9.3542) (14.0589, 8.112) knots 0 0 0 0 1 1 1 1
  spline S73 degree 3 poles (14.0589, 8.112) (16.0454, 6.08) (16.2118, 5.4384) (16.2118, 4.9965) knots 0 0 0 0 1 1 1 1
  spline S74 degree 3 poles (16.2118, 4.9965) (16.2118, 3.5487) (14.5957, 3.5344) (13.6305, 3.526) knots 0 0 0 0 1 1 1 1
  spline S75 degree 3 poles (13.6305, 3.526) (13.3133, 3.5236) (12.8214, 3.5191) (12.5542, 3.4646) knots 0 0 0 0 1 1 1 1
  spline S76 degree 3 poles (12.5542, 3.4646) (12.5574, 3.1542) (12.5656, 2.682) (12.5754, 2.0951) knots 0 0 0 0 1 1 1 1
  spline S77 degree 3 poles (12.5754, 2.0951) (12.6233, -0.6783) (12.7122, -5.8403) (12.5174, -8.8801) knots 0 0 0 0 1 1 1 1
  spline S78 degree 3 poles (12.5174, -8.8801) (12.4198, -10.4017) (11.5454, -11.527) (10.056, -12.049) knots 0 0 0 0 1 1 1 1
  spline S79 degree 3 poles (10.056, -12.049) (7.7541, -12.8544) (3.8738, -12.1151) (0.2736, -10.5141) knots 0 0 0 0 1 1 1 1
  spline S80 degree 3 poles (0.2736, -10.5141) (-1.456, -11.301) (-3.1726, -11.9154) (-4.5524, -12.4088) knots 0 0 0 0 1 1 1 1
  spline S81 degree 3 poles (-4.5524, -12.4088) (-5.7084, -12.8224) (-6.8784, -13.1637) (-8.0468, -13.4428) knots 0 0 0 0 1 1 1 1
  spline S82 degree 3 poles (-8.0468, -13.4428) (-2.3876, -17.0872) (11.9745, -15.5005) (24.9499, -12.1448) knots 0 0 0 0 1 1 1 1
  spline S83 degree 3 poles (-9.6697, -11.9238) (-10.2428, -11.0994) (-10.5243, -10.131) (-10.5243, -8.9981) knots 0 0 0 0 1 1 1 1
  spline S84 degree 3 poles (-10.5243, -8.9981) (-10.5243, -7.1717) (-10.4711, -3.009) (-10.4323, 0.0303) knots 0 0 0 0 1 1 1 1
  spline S85 degree 3 poles (-10.4323, 0.0303) (-10.409, 1.849) (-10.391, 3.2855) (-10.391, 3.667) knots 0 0 0 0 1 1 1 1
  spline S86 degree 3 poles (-10.391, 3.667) (-10.391, 4.0861) (-10.5429, 4.4541) (-10.8302, 4.7309) knots 0 0 0 0 1 1 1 1
  spline S87 degree 3 poles (-10.8302, 4.7309) (-11.2863, 5.1706) (-11.9539, 5.2548) (-12.6582, 5.2548) knots 0 0 0 0 1 1 1 1
  spline S88 degree 3 poles (-12.6582, 5.2548) (-12.8786, 5.2548) (-13.1024, 5.2468) (-13.3244, 5.2384) knots 0 0 0 0 1 1 1 1
  spline S89 degree 3 poles (-13.3244, 5.2384) (-13.5546, 5.2299) (-13.8758, 5.2183) (-14.1393, 5.2265) knots 0 0 0 0 1 1 1 1
  spline S90 degree 3 poles (-14.1393, 5.2265) (-13.3488, 6.2324) (-11.0273, 8.5152) (-7.9499, 11.0116) knots 0 0 0 0 1 1 1 1
  spline S91 degree 3 poles (-7.9499, 11.0116) (-3.4406, 14.67) (-0.834, 15.9677) (0.0278, 15.9677) knots 0 0 0 0 1 1 1 1
  spline S92 degree 3 poles (0.0278, 15.9677) (0.9538, 15.9677) (3.6158, 14.679) (8.0687, 11.047) knots 0 0 0 0 1 1 1 1
  spline S93 degree 3 poles (8.0687, 11.047) (11.009, 8.6491) (13.2302, 6.4306) (14.0586, 5.3699) knots 0 0 0 0 1 1 1 1
  spline S94 degree 3 poles (14.0586, 5.3699) (13.9052, 5.3648) (13.747, 5.3638) (13.6147, 5.3624) knots 0 0 0 0 1 1 1 1
  spline S95 degree 3 poles (13.6147, 5.3624) (12.6018, 5.3537) (10.7167, 5.337) (10.7167, 3.6667) knots 0 0 0 0 1 1 1 1
  spline S96 degree 3 poles (10.7167, 3.6667) (10.7167, 3.3783) (10.7265, 2.8124) (10.7394, 2.0634) knots 0 0 0 0 1 1 1 1
  spline S97 degree 3 poles (10.7394, 2.0634) (10.7865, -0.6841) (10.8749, -5.7977) (10.6847, -8.7631) knots 0 0 0 0 1 1 1 1
  spline S98 degree 3 poles (10.6847, -8.7631) (10.6341, -9.5556) (10.2531, -10.0345) (9.4491, -10.316) knots 0 0 0 0 1 1 1 1
  spline S99 degree 3 poles (9.4491, -10.316) (7.8523, -10.8748) (5.1641, -10.4427) (2.4437, -9.4235) knots 0 0 0 0 1 1 1 1
  spline S100 degree 3 poles (2.4437, -9.4235) (5.996, -7.4357) (9.0009, -4.5801) (8.4212, -0.3631) knots 0 0 0 0 1 1 1 1
  spline S101 degree 3 poles (8.4212, -0.3631) (8.1023, 1.9559) (6.2775, 3.3887) (3.6526, 3.3887) knots 0 0 0 0 1 1 1 1
  spline S102 degree 3 poles (3.6526, 3.3887) (3.6298, 3.3887) (3.6071, 3.3884) (3.5843, 3.3881) knots 0 0 0 0 1 1 1 1
  spline S103 degree 3 poles (3.5843, 3.3881) (2.3916, 3.377) (1.3282, 3.1151) (0.431, 2.6891) knots 0 0 0 0 1 1 1 1
  spline S104 degree 3 poles (0.431, 2.6891) (0.013, 3.1452) (-0.4614, 3.5519) (-0.9864, 3.8773) knots 0 0 0 0 1 1 1 1
  spline S105 degree 3 poles (-0.9864, 3.8773) (-2.518, 4.8275) (-4.2331, 4.9148) (-5.8145, 4.1237) knots 0 0 0 0 1 1 1 1
  spline S106 degree 3 poles (-5.8145, 4.1237) (-7.185, 3.4387) (-8.0645, 2.2464) (-8.3579, 0.6759) knots 0 0 0 0 1 1 1 1
  spline S107 degree 3 poles (-8.3579, 0.6759) (-8.7656, -1.5045) (-7.9317, -4.2578) (-6.3302, -6.0199) knots 0 0 0 0 1 1 1 1
  spline S108 degree 3 poles (-6.3302, -6.0199) (-5.184, -7.2815) (-3.6235, -8.4464) (-1.8918, -9.4251) knots 0 0 0 0 1 1 1 1
  spline S109 degree 3 poles (-1.8918, -9.4251) (-2.9475, -9.8635) (-4.0502, -10.2792) (-5.1708, -10.6798) knots 0 0 0 0 1 1 1 1
  spline S110 degree 3 poles (-5.1708, -10.6798) (-6.6593, -11.2124) (-8.1698, -11.619) (-9.6697, -11.9238) knots 0 0 0 0 1 1 1 1
  spline S111 degree 3 poles (0.2381, -8.47) (-1.8124, -7.4619) (-3.711, -6.1713) (-4.9718, -4.7841) knots 0 0 0 0 1 1 1 1
  spline S112 degree 3 poles (-4.9718, -4.7841) (-6.1918, -3.4418) (-6.8569, -1.2871) (-6.5532, 0.3388) knots 0 0 0 0 1 1 1 1
  spline S113 degree 3 poles (-6.5532, 0.3388) (-6.3667, 1.3365) (-5.8417, 2.0573) (-4.9935, 2.4814) knots 0 0 0 0 1 1 1 1
  spline S114 degree 3 poles (-4.9935, 2.4814) (-4.5331, 2.7113) (-4.0727, 2.8267) (-3.6137, 2.8267) knots 0 0 0 0 1 1 1 1
  spline S115 degree 3 poles (-3.6137, 2.8267) (-3.0562, 2.8267) (-2.5016, 2.6566) (-1.9547, 2.3174) knots 0 0 0 0 1 1 1 1
  spline S116 degree 3 poles (-1.9547, 2.3174) (-1.6576, 2.1329) (-1.378, 1.9078) (-1.1213, 1.6546) knots 0 0 0 0 1 1 1 1
  spline S117 degree 3 poles (-1.1213, 1.6546) (-2.0106, 0.8423) (-2.5575, -0.1623) (-2.6741, -1.1476) knots 0 0 0 0 1 1 1 1
  spline S118 degree 3 poles (-2.6741, -1.1476) (-2.8226, -2.4025) (-2.3709, -3.4921) (-1.4354, -4.1366) knots 0 0 0 0 1 1 1 1
  spline S119 degree 3 poles (-1.4354, -4.1366) (-0.594, -4.7158) (0.49, -4.8065) (1.3266, -4.3687) knots 0 0 0 0 1 1 1 1
  spline S120 degree 3 poles (1.3266, -4.3687) (2.095, -3.9665) (2.5379, -3.1915) (2.5416, -2.2419) knots 0 0 0 0 1 1 1 1
  spline S121 degree 3 poles (2.5416, -2.2419) (2.5453, -1.2434) (2.1934, -0.0065) (1.5452, 1.1455) knots 0 0 0 0 1 1 1 1
  spline S122 degree 3 poles (1.5452, 1.1455) (2.1995, 1.4016) (2.9168, 1.5458) (3.6012, 1.5522) knots 0 0 0 0 1 1 1 1
  spline S123 degree 3 poles (3.6012, 1.5522) (4.422, 1.5614) (6.3296, 1.3638) (6.6016, -0.6129) knots 0 0 0 0 1 1 1 1
  spline S124 degree 3 poles (6.6016, -0.6129) (7.0789, -4.0848) (4.2444, -6.5181) (0.2381, -8.47) knots 0 0 0 0 1 1 1 1
  spline S125 degree 3 poles (-0.8501, -1.3633) (-0.7808, -0.7772) (-0.4723, -0.2544) (-0.0177, 0.1814) knots 0 0 0 0 1 1 1 1
  spline S126 degree 3 poles (-0.0177, 0.1814) (0.4437, -0.6544) (0.7072, -1.5397) (0.7046, -2.2353) knots 0 0 0 0 1 1 1 1
  spline S127 degree 3 poles (0.7046, -2.2353) (0.703, -2.6221) (0.531, -2.7121) (0.4747, -2.7415) knots 0 0 0 0 1 1 1 1
  spline S128 degree 3 poles (0.4747, -2.7415) (0.2778, -2.8455) (-0.0833, -2.8375) (-0.394, -2.6243) knots 0 0 0 0 1 1 1 1
  spline S129 degree 3 poles (-0.394, -2.6243) (-0.6493, -2.4483) (-0.9361, -2.0866) (-0.8501, -1.3633) knots 0 0 0 0 1 1 1 1
  spline S130 degree 3 poles (15.0892, 25.2753) (10.6786, 27.9245) (5.5158, 29.4485) (0, 29.4485) knots 0 0 0 0 1 1 1 1
  spline S131 degree 3 poles (0, 29.4485) (-5.9163, 29.4485) (-11.4263, 27.6951) (-16.0375, 24.681) knots 0 0 0 0 1 1 1 1
  spline S132 degree 3 poles (-16.0375, 24.681) (-16.1756, 25.4377) (-16.1512, 26.2278) (-16.3626, 26.9715) knots 0 0 0 0 1 1 1 1
  spline S133 degree 3 poles (-16.3626, 26.9715) (-14.4912, 28.3087) (-12.1571, 29.0233) (-9.9621, 29.6245) knots 0 0 0 0 1 1 1 1
  spline S134 degree 3 poles (-9.9621, 29.6245) (-7.6245, 30.2537) (-5.2549, 30.7574) (-2.8633, 31.1329) knots 0 0 0 0 1 1 1 1
  spline S135 degree 3 poles (-2.8633, 31.1329) (0.4927, 31.6877) (3.8798, 32.0359) (7.2784, 32.1753) knots 0 0 0 0 1 1 1 1
  spline S136 degree 3 poles (7.2784, 32.1753) (8.1428, 32.2084) (9.0149, 32.2304) (9.8891, 32.2325) knots 0 0 0 0 1 1 1 1
  spline S137 degree 3 poles (9.8891, 32.2325) (12.3785, 32.2386) (14.8857, 32.0735) (17.3014, 31.5329) knots 0 0 0 0 1 1 1 1
  spline S138 degree 3 poles (17.3014, 31.5329) (16.6222, 29.6951) (16.0986, 27.8033) (15.3694, 25.9865) knots 0 0 0 0 1 1 1 1
  spline S139 degree 3 poles (15.3694, 25.9865) (15.3051, 25.8219) (15.2183, 25.5039) (15.0892, 25.2753) knots 0 0 0 0 1 1 1 1
  spline S140 degree 3 poles (-17.3858, 42.6187) (-15.9779, 42.6266) (-14.5732, 42.4695) (-13.2006, 42.1499) knots 0 0 0 0 1 1 1 1
  spline S141 degree 3 poles (-13.2006, 42.1499) (-9.7398, 41.3773) (-6.3212, 39.7845) (-3.7917, 37.2709) knots 0 0 0 0 1 1 1 1
  spline S142 degree 3 poles (-3.7917, 37.2709) (-2.4138, 35.9419) (-1.3896, 34.2917) (-0.8033, 32.4703) knots 0 0 0 0 1 1 1 1
  spline S143 degree 3 poles (-0.8033, 32.4703) (-2.4051, 32.0941) (-4.0315, 31.8552) (-5.6438, 31.5697) knots 0 0 0 0 1 1 1 1
  spline S144 degree 3 poles (-5.6438, 31.5697) (-7.6824, 31.2228) (-9.6962, 30.7413) (-11.6716, 30.1298) knots 0 0 0 0 1 1 1 1
  spline S145 degree 3 poles (-11.6716, 30.1298) (-12.8622, 29.7554) (-14.0351, 29.3311) (-15.1963, 28.8715) knots 0 0 0 0 1 1 1 1
  spline S146 degree 3 poles (-15.1963, 28.8715) (-15.2419, 30.7167) (-15.5263, 32.5487) (-16.0475, 34.3208) knots 0 0 0 0 1 1 1 1
  spline S147 degree 3 poles (-16.0475, 34.3208) (-16.6412, 36.1883) (-17.6345, 37.9036) (-18.9579, 39.3479) knots 0 0 0 0 1 1 1 1
  spline S148 degree 3 poles (-18.9579, 39.3479) (-19.7874, 40.2433) (-20.7137, 41.0434) (-21.7154, 41.7405) knots 0 0 0 0 1 1 1 1
  spline S149 degree 3 poles (-21.7154, 41.7405) (-20.5454, 42.2787) (-19.2781, 42.5748) (-17.9893, 42.6052) knots 0 0 0 0 1 1 1 1
  spline S150 degree 3 poles (-17.9893, 42.6052) (-17.7882, 42.6129) (-17.5869, 42.6174) (-17.3858, 42.6187) knots 0 0 0 0 1 1 1 1
  spline S151 degree 3 poles (13.2858, 49.383) (13.8446, 49.3759) (14.4039, 49.3513) (14.964, 49.3044) knots 0 0 0 0 1 1 1 1
  spline S152 degree 3 poles (14.964, 49.3044) (17.4106, 49.0978) (19.8101, 48.4787) (21.9239, 47.2254) knots 0 0 0 0 1 1 1 1
  spline S153 degree 3 poles (21.9239, 47.2254) (19.9578, 46.162) (18.1584, 44.8145) (16.5888, 43.2217) knots 0 0 0 0 1 1 1 1
  spline S154 degree 3 poles (16.5888, 43.2217) (16.1832, 42.8036) (15.7988, 42.3679) (15.4355, 41.9146) knots 0 0 0 0 1 1 1 1
  spline S155 degree 3 poles (15.4355, 41.9146) (15.2741, 41.7136) (15.1707, 41.5096) (14.9961, 41.327) knots 0 0 0 0 1 1 1 1
  spline S156 degree 3 poles (14.9961, 41.327) (14.7947, 41.1516) (14.5558, 41.0248) (14.2976, 40.9566) knots 0 0 0 0 1 1 1 1
  spline S157 degree 3 poles (14.2976, 40.9566) (13.3689, 40.6761) (12.3955, 40.5467) (11.4615, 40.2795) knots 0 0 0 0 1 1 1 1
  spline S158 degree 3 poles (11.4615, 40.2795) (10.0309, 39.8803) (8.6728, 39.255) (7.4396, 38.4274) knots 0 0 0 0 1 1 1 1
  spline S159 degree 3 poles (7.4396, 38.4274) (5.3441, 37.004) (3.6692, 35.0725) (2.2749, 32.9741) knots 0 0 0 0 1 1 1 1
  spline S160 degree 3 poles (2.2749, 32.9741) (2.2617, 32.9561) (2.2548, 32.9347) (2.2548, 32.9122) knots 0 0 0 0 1 1 1 1
  spline S161 degree 3 poles (2.2548, 32.9122) (2.2548, 32.9003) (2.2598, 32.8894) (2.2635, 32.8789) knots 0 0 0 0 1 1 1 1
  spline S162 degree 3 poles (2.2635, 32.8789) (1.6957, 32.8241) (1.129, 32.7585) (0.5625, 32.6878) knots 0 0 0 0 1 1 1 1
  spline S163 degree 3 poles (0.5625, 32.6878) (-1.1187, 36.2658) (-4.0775, 39.1823) (-7.5885, 40.9751) knots 0 0 0 0 1 1 1 1
  spline S164 degree 3 poles (-7.5885, 40.9751) (-7.8557, 41.1119) (-8.1269, 41.2402) (-8.4003, 41.3638) knots 0 0 0 0 1 1 1 1
  spline S165 degree 3 poles (-8.4003, 41.3638) (-8.2957, 41.373) (-8.1992, 41.3966) (-8.1362, 41.4569) knots 0 0 0 0 1 1 1 1
  spline S166 degree 3 poles (-8.1362, 41.4569) (-5.2549, 44.2562) (-1.8952, 46.5554) (1.9333, 47.8492) knots 0 0 0 0 1 1 1 1
  spline S167 degree 3 poles (1.9333, 47.8492) (3.9854, 48.521) (6.1103, 48.9478) (8.2627, 49.1195) knots 0 0 0 0 1 1 1 1
  spline S168 degree 3 poles (8.2627, 49.1195) (9.9375, 49.2703) (11.6091, 49.4045) (13.2858, 49.383) knots 0 0 0 0 1 1 1 1
  spline S169 degree 3 poles (18.7793, 40.5219) (19.7985, 40.5409) (20.8161, 40.4515) (21.821, 40.2763) knots 0 0 0 0 1 1 1 1
  spline S170 degree 3 poles (21.821, 40.2763) (20.7441, 39.1979) (19.5858, 38.1991) (18.5547, 37.0728) knots 0 0 0 0 1 1 1 1
  spline S171 degree 3 poles (18.5547, 37.0728) (17.3768, 35.7829) (16.4269, 34.3031) (15.7398, 32.6979) knots 0 0 0 0 1 1 1 1
  spline S172 degree 3 poles (15.7398, 32.6979) (11.6861, 33.1971) (7.5962, 33.2929) (3.5287, 32.9852) knots 0 0 0 0 1 1 1 1
  spline S173 degree 3 poles (3.5287, 32.9852) (4.3199, 33.88) (4.953, 34.9093) (5.7571, 35.7924) knots 0 0 0 0 1 1 1 1
  spline S174 degree 3 poles (5.7571, 35.7924) (6.7577, 36.8569) (7.9462, 37.7279) (9.2628, 38.3615) knots 0 0 0 0 1 1 1 1
  spline S175 degree 3 poles (9.2628, 38.3615) (11.7972, 39.6606) (14.7688, 40.2483) (17.5892, 40.4547) knots 0 0 0 0 1 1 1 1
  spline S176 degree 3 poles (17.5892, 40.4547) (17.9856, 40.492) (18.3825, 40.5142) (18.7793, 40.5219) knots 0 0 0 0 1 1 1 1
  arc A1 (-16.7419, 28.4371) -> (-20.9379, 20.6659) centre (-19.6023, 24.9631) ccw
  arc A2 (-15.4877, 23.1409) -> (-15.4877, 23.1409) centre (-19.6023, 24.9631) ccw
  arc A3 (-17.6686, 26.5476) -> (-18.8791, 22.57) centre (-19.6023, 24.9631) ccw
  arc A4 (20.6134, 20.9906) -> (18.4776, 29.6504) centre (18.9617, 25.1765) ccw
  arc A5 (18.7395, 22.6864) -> (17.7492, 27.3628) centre (18.9617, 25.1765) ccw
  dimension "d10" = 60
  dimension "d13" = 5
  constraint coincident A0.centre origin
  constraint concentric A1 A3
  constraint coincident S5 A1.start
  constraint coincident S59 A2.start
  constraint concentric A1 A2
  constraint coincident S49 A1.end
  constraint coincident S49 A3.end
  constraint coincident S1 A3.start
  constraint coincident S46 A4.start
  constraint coincident S43 A4.end
  constraint coincident S43 A5.end
  constraint coincident S46 A5.start
  measures "d10" diameter of A0
  measures "d13" diameter of A3
extrude "Extrusion3" add sketch "Skizze2" against normal blind 1.5 separate body contours S0 S1 S2 S3 S4 S5 S49 S59 S131 S132 S133 A2 | S1 S2 S3 S4 S5 S49 A1 A2 A3 | S5 S6 S7 S8 S9 S10 S11 S12 S13 S14 S15 S16 S17 S18 S19 S20 S21 S22 S23 S24 S25 S26 S27 S28 S29 S30 S31 S32 S33 S34 S35 S36 S37 S38 S39 S40 S41 S42 S43 S44 S45 S46 S47 S48 S49 S56 S57 S58 L0 S59 S60 S61 S62 S63 S64 S65 S66 S67 S68 S69 S70 S71 S72 S73 S74 S75 S76 S77 S78 S79 S80 S81 S82 S130 S131 S133 S134 S135 S136 S137 S138 S139 A2 | S56 S57 S58 L0 S59 S60 S61 S62 S63 S64 S65 S66 S67 S68 S69 S70 S71 S72 S73 S74 S75 S76 S77 S78 S79 S80 S81 S82 A2 | S59 A2 | S131 S132 S133 A2 | S130 S131 S133 S134 S135 S136 S137 S138 S139 A2 | S43 S46 A4 A5 | S50 S51 S52 S53 S54 S55 | S83 S84 S85 S86 S87 S88 S89 S90 S91 S92 S93 S94 S95 S96 S97 S98 S99 S100 S101 S102 S103 S104 S105 S106 S107 S108 S109 S110 | S111 S112 S113 S114 S115 S116 S117 S118 S119 S120 S121 S122 S123 S124 | S125 S126 S127 S128 S129 | S140 S141 S142 S143 S144 S145 S146 S147 S148 S149 S150 | S151 S152 S153 S154 S155 S156 S157 S158 S159 S160 S161 S162 S163 S164 S165 S166 S167 S168 | S169 S170 S171 S172 S173 S174 S175 S176 makes body 2
extrude "Extrusion4" add sketch "Skizze2" along normal blind 1 contours S0 S1 S2 S3 S4 S5 S49 S59 S131 S132 S133 A2 | S1 S2 S3 S4 S5 S49 A1 A2 A3 | S5 S6 S7 S8 S9 S10 S11 S12 S13 S14 S15 S16 S17 S18 S19 S20 S21 S22 S23 S24 S25 S26 S27 S28 S29 S30 S31 S32 S33 S34 S35 S36 S37 S38 S39 S40 S41 S42 S43 S44 S45 S46 S47 S48 S49 S56 S57 S58 L0 S59 S60 S61 S62 S63 S64 S65 S66 S67 S68 S69 S70 S71 S72 S73 S74 S75 S76 S77 S78 S79 S80 S81 S82 S130 S131 S133 S134 S135 S136 S137 S138 S139 A2 | S43 S46 A4 A5 bodies 2